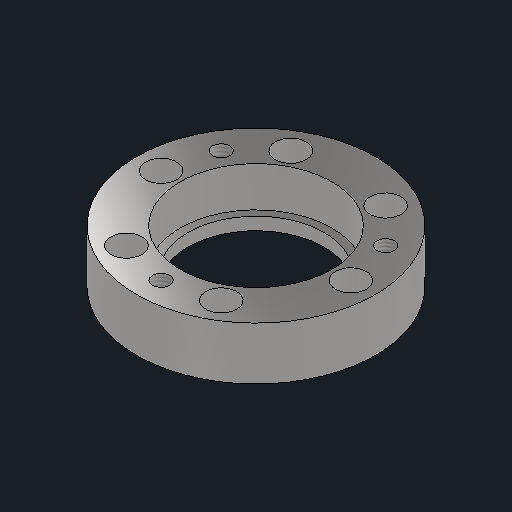
# Autodesk Inventor part: ICF34_frange
Saved by Autodesk Inventor 2027.1 (Build 311270010, 270A)
## iProperties
Created: 2026-08-19
Part Number: ICF34_frange
Material: ステンレス鋼
Document SubType Name: Modeling
Designer: rkawa
Density: 8 g/cm^3
Appearance: 半つや出し
Mass: 27.1805 g
Surface Area: 31.0715 cm^2
Volume: 3.39756 cm^3
Author: rkawa
Autodesk Inventor part; units mm, degrees
ref_plane "YZ Plane" through (0, 0, 0) normal (1, 0, 0) x (0, 1, 0)
ref_plane "XZ Plane" through (0, 0, 0) normal (0, 1, 0) x (-1, 0, 0)
ref_plane "XY Plane" through (0, 0, 0) normal (0, 0, 1) x (1, 0, 0)
sketch "スケッチ1" plane through (0, 0, 0) normal (0, 1, 0) x (-1, 0, 0)
  circle A0 centre (0, 0) radius 17
  circle A1 centre (0, 0) radius 9.7
  dimension "d0" = 34
  dimension "d1" = 19.4
  constraints: 2 centre point, 2 coincident
  measures "d0" diameter of A0
  measures "d1" diameter of A1
extrude "押し出し1" add sketch "スケッチ1" along normal blind 7.5
sketch "スケッチ2" plane through (0, 7.5, 0) normal (0, 1, 0) x (1, 0, 0)
  circle A0 centre (0, 0) radius 13.5
  point P0 (-13.5, 0)
  point P1 (-6.75, -11.6913)
  point P2 (6.75, -11.6913)
  point P3 (13.5, 0)
  point P4 (6.75, 11.6913)
  point P5 (-6.75, 11.6913)
  point P6 (-11.6913, 6.75)
  point P7 (0, -13.5)
  point P8 (11.6913, 6.75)
  dimension "d4" = 27
  dimension "d7" = 360
  dimension "d19" = 30
  dimension "d22" = 360
  constraints: 2 point on circle, 1 centre point, 1 coincident, 11 other
  measures "d4" diameter of A0
hole "穴1" at (-13.5, 7.5, 0) at (-6.75, 7.5, 11.6913) at (6.75, 7.5, 11.6913) at (13.5, 7.5, 0) at (6.75, 7.5, -11.6913) at (-6.75, 7.5, -11.6913) direction (0, -1, 0) diameter 4.4 end through all
sketch "スケッチ3" plane through (0, 7.5, 0) normal (0, 1, 0) x (1, 0, 0)
  circle A0 centre (0, 0) radius 10.8
  dimension "d16" = 21.6
  constraints: 1 centre point, 1 coincident
  measures "d16" diameter of A0
extrude "押し出し2" cut sketch "スケッチ3" against normal blind 5.7
hole "穴2" at (-11.6913, 7.5, -6.75) at (0, 7.5, 13.5) at (11.6913, 7.5, -6.75) direction (0, -1, 0) diameter 2.459 end through all thread size "M3x0.5" class "6H" standard "ISO Metric profile"
